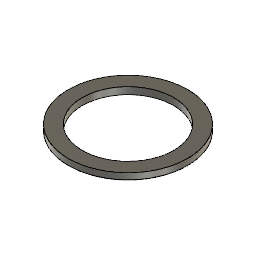
astra-sv-solar-filter-retainer (Autodesk Fusion 360 design; units mm, degrees)
part number: 2026-01-25-13-45-08-993
Autodesk Fusion 360 part; units mm, degrees
sketch "Sketch1" plane through (0, 0, 0) normal (0, 1, 0) x (1, 0, 0)
  line L0 (-26, 0) -> (-33.5, 0)
  line L1 (-34, -0.5) -> (-34, -4)
  line L2 (-34, -4) -> (-26, -4)
  line L3 (-26, -4) -> (-26, 0)
  arc A0 (-33.5, 0) -> (-34, -0.5) centre (-33.5, -0.5) ccw
  dimension "d1" = 0.5
  constraint horizontal L0
  constraint perpendicular L0 L1
  constraint perpendicular L1 L2
  constraint perpendicular L0 L3
  constraint tangent L0 A0
  constraint tangent L1 A0
  measures "d1" radius of A0
revolve "Revolve1" add sketch "Sketch1" angle 360 about axis through (0, 0, 1.75) along (0, 0, 1)
move_body "Move1" bodies 1 to x (1, 0, 0) y (0, 1, 0) z (0, 0, 1) at (0, 0, -4)
named bodies: "astra-sv-solar-filter-retainer"
